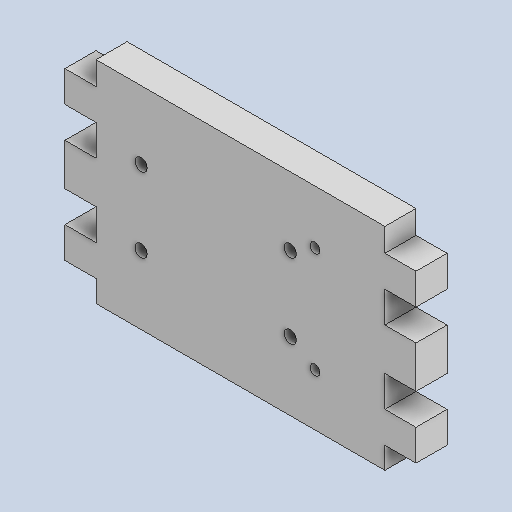
# Autodesk Inventor part: NeckTop
Saved by Autodesk Inventor 2025.2 (Build 292293000, 293)
## iProperties
Created: 2025-06-29
Part Number: NeckTop
Material: Generic
Document SubType Name: Modeling
Designer: ricoa
Density: 1 g/cm^3
Appearance: Default
Author: ricoa
Autodesk Inventor part; units mm, degrees
ref_plane "YZ Plane" through (0, 0, 0) normal (1, 0, 0) x (0, 1, 0)
ref_plane "XZ Plane" through (0, 0, 0) normal (0, 1, 0) x (-1, 0, 0)
ref_plane "XY Plane" through (0, 0, 0) normal (0, 0, 1) x (1, 0, 0)
sketch "Sketch1" plane through (0, 0, 0) normal (0, 0, 1) x (1, 0, 0)
  circle A0 centre (-39.25, 2.5) radius 1 projected
  circle A1 centre (-39.25, 14.5) radius 1 projected
  circle A2 centre (-15.25, 2.5) radius 1 projected
  circle A3 centre (-15.25, 14.5) radius 1 projected
  line L0 (5, 11.75) -> (5, 5) projected
  line L1 (0, 5) -> (5, 5) projected
  line L2 (0, 11.75) -> (5, 11.75) projected
  line L3 (0, 5) -> (0, 0) projected
  line L4 (0, 16.75) -> (0, 11.75) projected
  line L5 (-46.5, 0) -> (-44.5, 0) projected
  line L6 (-44.5, 16.75) -> (-46.5, 16.75) projected
  line L7 (0, 0) -> (-2, 0)
  line L8 (0, 16.75) -> (-2, 16.75)
  line L9 (-51.5, 5) -> (-46.5, 5)
  line L10 (-46.5, 11.75) -> (-51.5, 11.75)
  line L11 (-46.5, 0) -> (-46.5, 5)
  line L12 (-46.5, 11.75) -> (-46.5, 16.75)
  line L13 (-51.5, 5) -> (-51.5, 11.75)
  line L14 (-2.1036, -8.5) -> (-19.25, -8.5) projected
  line L15 (-44.3964, 25.5) -> (-2.1036, 25.5) projected
  line L16 (0, -8.5) -> (-46.5, -8.5)
  line L17 (-46.5, 25.5) -> (0, 25.5)
  line L18 (0, 0) -> (5, 0)
  line L19 (5, 0) -> (5, -5)
  line L20 (5, -5) -> (0, -5)
  line L21 (-46.5, 0) -> (-51.5, 0)
  line L22 (-51.5, 0) -> (-51.5, -5)
  line L23 (-51.5, -5) -> (-46.5, -5)
  line L24 (0, 16.75) -> (5, 16.75)
  line L25 (5, 16.75) -> (5, 21.75)
  line L26 (5, 21.75) -> (0, 21.75)
  line L27 (-46.5, 21.75) -> (-51.5, 21.75)
  line L28 (-51.5, 21.75) -> (-51.5, 16.75)
  line L29 (-46.5, 16.75) -> (-51.5, 16.75)
  line L30 (-46.5, -8.5) -> (-46.5, -5)
  line L31 (-46.5, 0) -> (-46.5, 5)
  line L32 (-46.5, 11.75) -> (-46.5, 16.75)
  line L33 (-46.5, 21.75) -> (-46.5, 25.5)
  line L34 (0, 25.5) -> (0, 21.75)
  line L35 (0, 16.75) -> (0, 11.75)
  line L36 (0, 5) -> (0, 0)
  line L37 (0, -5) -> (0, -8.5)
  dimension "d4" = 5
  dimension "d5" = 5
  constraints: 60 end point, 18 parallel, 13 perpendicular, 6 horizontal, 5 point on line, 1 vertical
  measures "d4" distance of L18.end L19.end
  measures "d5" distance of L24.end L25.end
extrude "Extrusion1" add sketch "Sketch1" along normal blind 5
sketch "Sketch2" plane through (0, 0, 5) normal (0, 0, 1) x (1, 0, 0)
  line L0 (5, 5) -> (5, 11.75) projected
  line L1 (5, 8.375) -> (-11.25, 8.375)
  line L2 (-11.25, 8.375) -> (-11.25, -0.125)
  line L3 (-11.25, -0.125) -> (-11.25, 16.875)
  circle A0 centre (-15.6937, 23.9941) radius 0.7835 projected
  circle A1 centre (-15.6937, 6.9941) radius 0.7835 projected
  circle A2 centre (-11.25, 16.875) radius 0.8
  circle A3 centre (-11.25, -0.125) radius 0.8
  point P0 (0, 0)
  dimension "d6" = 16.25
  dimension "d7" = 8.5
  dimension "d8" = 17
  dimension "d9" = 1.6
  dimension "d10" = 1.6
  constraints: 6 end point, 2 centre point, 2 coincident, 1 horizontal, 1 midpoint, 1 perpendicular, 1 point on line
  measures "d6" distance of L1.start L1.end
  measures "d7" distance of L1.end L2.end
  measures "d8" distance of L2.end L3.end
  measures "d9" diameter of A2
  measures "d10" diameter of A3
extrude "Extrusion2" cut sketch "Sketch2" against normal blind 5 contours A3 | A2
body "Solid1"
